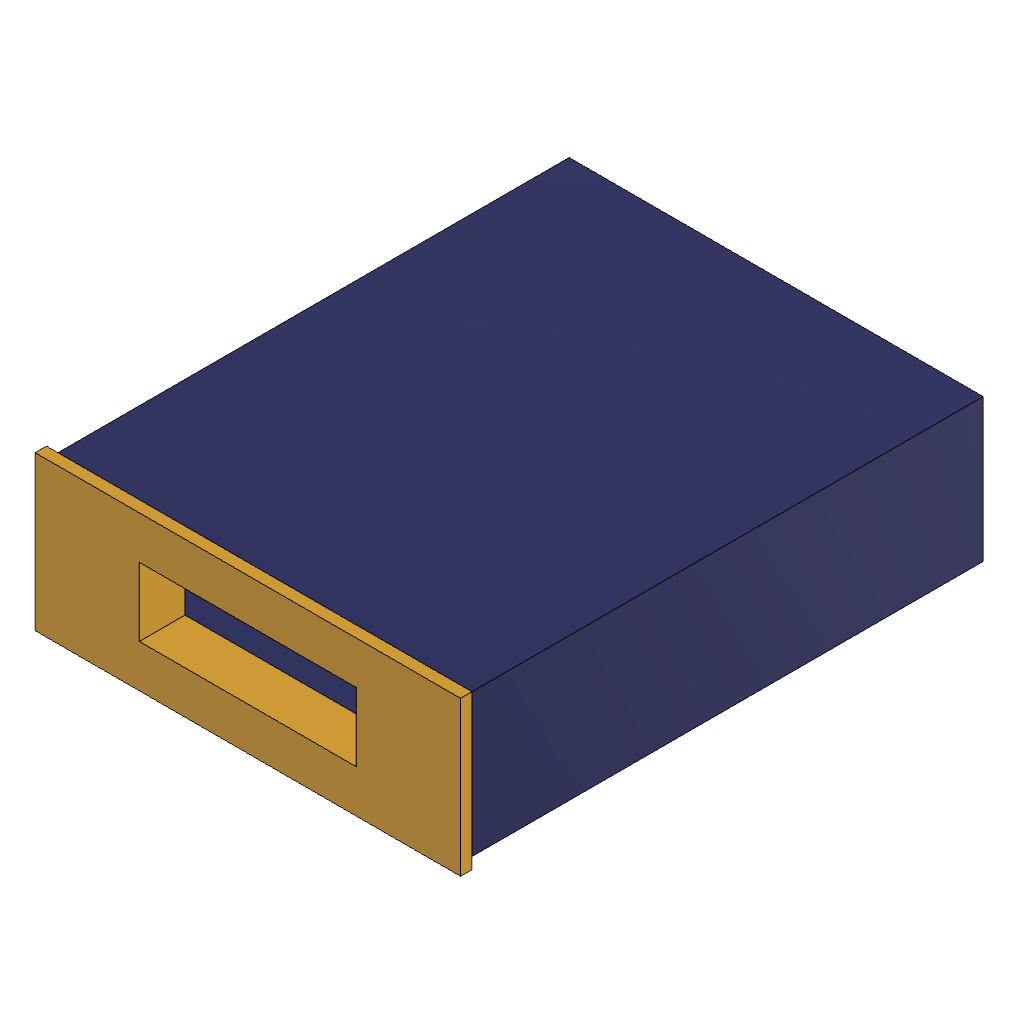
Aibot Case (Autodesk Fusion 360 design; units mm, degrees)
part number: 2026-11-24-14-18-23-545
Autodesk Fusion 360 part; units mm, degrees
sketch "Sketch11" plane through (0, 0, 0) normal (0, 0, 1) x (1, 0, 0)
  line L0 (0, 0) -> (72.5, 0)
  line L1 (72.5, 0) -> (72.5, 90.5)
  line L2 (72.5, 90.5) -> (0, 90.5)
  line L3 (0, 90.5) -> (0, 0)
extrude "Extrude11" add sketch "Sketch11" along normal blind 25 makes body 1
ref_plane "WorkPlane7" through (0, 0, 2) normal (0, 0, 1) x (1, 0, 0)
sketch "Sketch12" plane through (0, 0, 2) normal (0, 0, 1) x (1, 0, 0)
  line L0 (2, -2) -> (70.5, -2)
  line L1 (70.5, -2) -> (70.5, 88.5)
  line L2 (70.5, 88.5) -> (2, 88.5)
  line L3 (2, 88.5) -> (2, -2)
extrude "Extrude12" cut sketch "Sketch12" along normal blind 21 bodies 1
ref_plane "WorkPlane8" through (0, 89.5, 0) normal (0, 1, 0) x (0, 0, 1)
sketch "Sketch13" plane through (0, 89.5, 0) normal (0, 1, 0) x (1, 0, 0)
  line L0 (31.75, -10.75) -> (40.75, -10.75)
  line L1 (40.75, -10.75) -> (40.75, -14.25)
  line L2 (40.75, -14.25) -> (31.75, -14.25)
  line L3 (31.75, -14.25) -> (31.75, -10.75)
extrude "Extrude13" cut sketch "Sketch13" along normal blind 5 and the other way blind 5 bodies 1
ref_plane "WorkPlane9" through (0, -2, 0) normal (0, 1, 0) x (0, 0, 1)
sketch "Sketch14" plane through (0, -2, 0) normal (0, 1, 0) x (1, 0, 0)
  line L0 (-1, 1) -> (73.5, 1)
  line L1 (73.5, 1) -> (73.5, -26)
  line L2 (73.5, -26) -> (-1, -26)
  line L3 (-1, -26) -> (-1, 1)
extrude "Extrude14" add sketch "Sketch14" along normal blind 2 separate body makes body 2
ref_plane "WorkPlane10" through (0, -1, 0) normal (0, 1, 0) x (0, 0, 1)
sketch "Sketch15" plane through (0, -1, 0) normal (0, 1, 0) x (1, 0, 0)
  line L0 (2.1, -2.1) -> (70.4, -2.1)
  line L1 (70.4, -2.1) -> (70.4, -22.9)
  line L2 (70.4, -22.9) -> (2.1, -22.9)
  line L3 (2.1, -22.9) -> (2.1, -2.1)
extrude "Extrude15" add sketch "Sketch15" along normal blind 7 bodies 2
ref_plane "WorkPlane11" through (0, 2, 0) normal (0, 1, 0) x (0, 0, 1)
sketch "Sketch16" plane through (0, 2, 0) normal (0, 1, 0) x (1, 0, 0)
  line L0 (17.25, -6.5) -> (55.25, -6.5)
  line L1 (55.25, -6.5) -> (55.25, -18.5)
  line L2 (55.25, -18.5) -> (17.25, -18.5)
  line L3 (17.25, -18.5) -> (17.25, -6.5)
extrude "Extrude16" cut sketch "Sketch16" along normal blind 6 and the other way blind 6 bodies 2
ref_plane "WorkPlane12" through (0, 0, 22.8) normal (0, 0, 1) x (1, 0, 0)
sketch "Sketch17" plane through (0, 0, 22.8) normal (0, 0, 1) x (1, 0, 0)
  line L0 (31.25, 3) -> (41.25, 3)
  line L1 (41.25, 3) -> (41.25, 6)
  line L2 (41.25, 6) -> (31.25, 6)
  line L3 (31.25, 6) -> (31.25, 3)
extrude "Extrude17" add sketch "Sketch17" along normal blind 0.4 bodies 2
ref_plane "WorkPlane13" through (0, 0, 1.8) normal (0, 0, 1) x (1, 0, 0)
sketch "Sketch18" plane through (0, 0, 1.8) normal (0, 0, 1) x (1, 0, 0)
  line L0 (31.25, 3) -> (41.25, 3)
  line L1 (41.25, 3) -> (41.25, 6)
  line L2 (41.25, 6) -> (31.25, 6)
  line L3 (31.25, 6) -> (31.25, 3)
extrude "Extrude18" add sketch "Sketch18" along normal blind 0.4 bodies 2
ref_plane "WorkPlane14" through (0, 0, 23) normal (0, 0, 1) x (1, 0, 0)
sketch "Sketch19" plane through (0, 0, 23) normal (0, 0, 1) x (1, 0, 0)
  line L0 (30.75, 2.8) -> (41.75, 2.8)
  line L1 (41.75, 2.8) -> (41.75, 6.2)
  line L2 (41.75, 6.2) -> (30.75, 6.2)
  line L3 (30.75, 6.2) -> (30.75, 2.8)
extrude "Extrude19" cut sketch "Sketch19" along normal blind 0.5 bodies 1
ref_plane "WorkPlane15" through (0, 0, 1.5) normal (0, 0, 1) x (1, 0, 0)
sketch "Sketch20" plane through (0, 0, 1.5) normal (0, 0, 1) x (1, 0, 0)
  line L0 (30.75, 2.8) -> (41.75, 2.8)
  line L1 (41.75, 2.8) -> (41.75, 6.2)
  line L2 (41.75, 6.2) -> (30.75, 6.2)
  line L3 (30.75, 6.2) -> (30.75, 2.8)
extrude "Extrude20" cut sketch "Sketch20" along normal blind 0.5 bodies 1
named bodies: "Case", "Cap"
